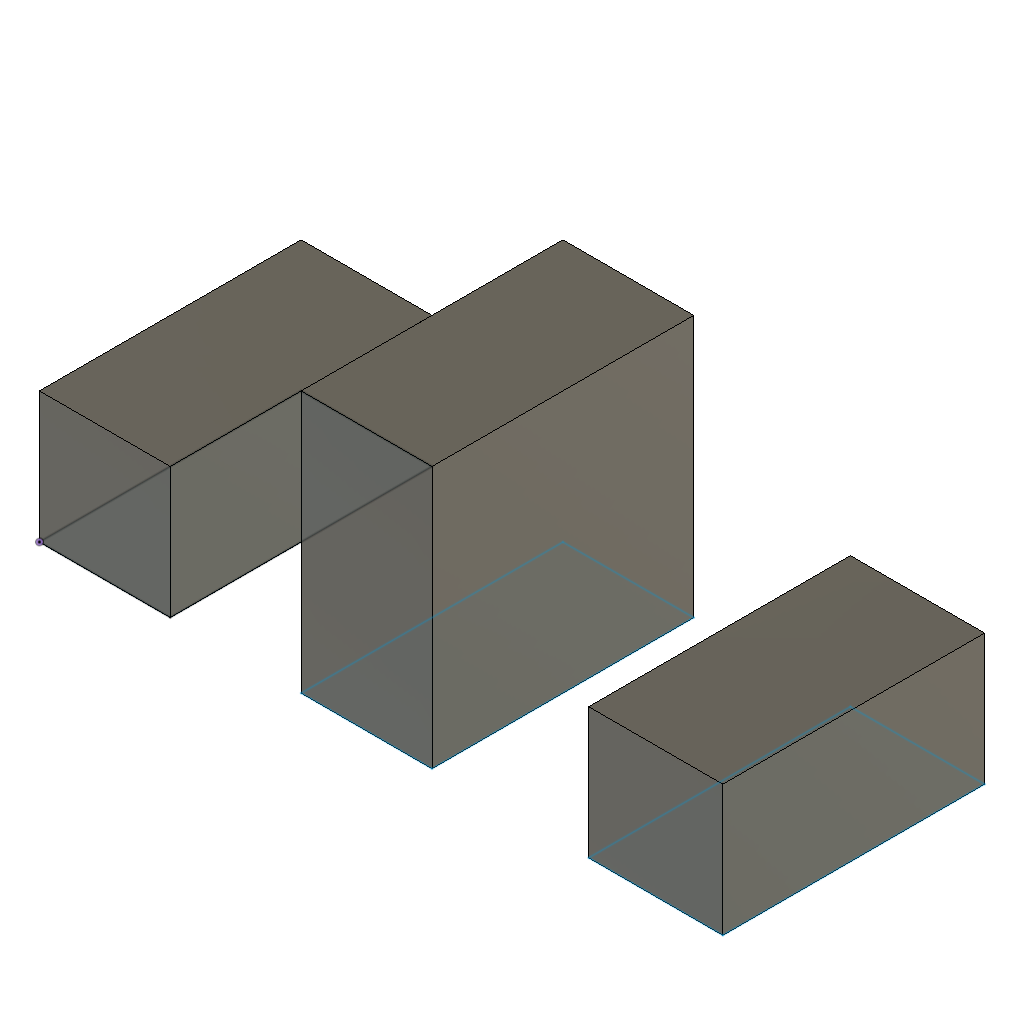
f2sc-test-shared-sketc (Autodesk Fusion 360 design; units mm, degrees)
part number: 2026-11-27-14-45-03-886
Autodesk Fusion 360 part; units mm, degrees
sketch "Sketch1" plane through (0, 0, 0) normal (0, 0, 1) x (1, 0, 0)
  line L0 (0, 0) -> (10, 0)
  line L1 (10, 0) -> (10, 20)
  line L2 (10, 20) -> (0, 20)
  line L3 (0, 20) -> (0, 0)
  line L4 (20, 0) -> (30, 0)
  line L5 (30, 0) -> (30, 20)
  line L6 (30, 20) -> (20, 20)
  line L7 (20, 20) -> (20, 0)
  line L8 (41.8838, 0.0869) -> (52.1375, 0.0869)
  line L9 (52.1375, 0.0869) -> (52.1375, 20.0869)
  line L10 (52.1375, 20.0869) -> (41.8838, 20.0869)
  line L11 (41.8838, 20.0869) -> (41.8838, 0.0869)
  dimension "d1" = 10
  dimension "d2" = 20
  dimension "d3" = 10
  dimension "d4" = 20
  dimension "d5" = 20
  constraint horizontal L0
  constraint vertical L1
  constraint horizontal L2
  constraint vertical L3
  constraint coincident L0.start L3.end
  constraint horizontal L4
  constraint vertical L5
  constraint horizontal L6
  constraint vertical L7
  constraint horizontal L8
  constraint vertical L9
  constraint horizontal L10
  constraint vertical L11
  measures "d1" distance of L0.start L0.end
  measures "d2" distance of L0.start L2.end
  measures "d3" distance of L4.start L4.end
  measures "d4" distance of L4.start L6.end
  measures "d5" distance of L8.start L10.end
extrude "Extrude1" add sketch "Sketch1" along normal blind 10 contours L0 L1 L2 L3 | L8 L9 L10 L11 makes body 1 at (0, 13.3333, 3.3333) makes body 2 at (45.3017, 13.4202, 0)
extrude "Extrude2" add sketch "Sketch1" along normal blind 20 separate body contours L4 L5 L6 L7 makes body 3
